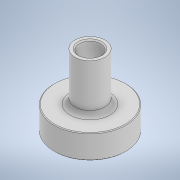
# Autodesk Inventor part: bague_portediodesimple
Saved by Autodesk Inventor 2021.5 (Build 255421000, 421)
## iProperties
Created: 2026-10-01
Part Number: bague_portediodesimple
Material: Générique
Document SubType Name: Modeling
Designer: Christophe
Density: 1 g/cm^3
Appearance: Par défaut
Author: Christophe
Autodesk Inventor part; units mm, degrees
ref_plane "YZ Plane" through (0, 0, 0) normal (1, 0, 0) x (0, 1, 0)
ref_plane "XZ Plane" through (0, 0, 0) normal (0, 1, 0) x (-1, 0, 0)
ref_plane "XY Plane" through (0, 0, 0) normal (0, 0, 1) x (1, 0, 0)
sketch "Esquisse1" plane through (0, 0, 0) normal (0, 1, 0) x (-1, 0, 0)
  circle A0 centre (0, 0) radius 15
  dimension "d0" = 30
  constraints: 1 centre point, 1 coincident
  measures "d0" diameter of A0
extrude "Extrusion1" add sketch "Esquisse1" along normal blind 10
chamfer "Chanfrein3" distance 0.3 angle 45 2 edges at (15, 10, 0) (15, 0, 0)
sketch "Esquisse3" plane through (0, 10, 0) normal (0, 1, 0) x (1, 0, 0)
  circle A0 centre (0, 0) radius 6.25
  dimension "d26" = 12.5
  constraints: 1 centre point, 1 coincident
  measures "d26" diameter of A0
extrude "Extrusion2" add sketch "Esquisse3" along normal blind 20
sketch "Esquisse4" plane through (0, 30, 0) normal (0, 1, 0) x (1, 0, 0)
  point P0 (0, 0)
hole "Perçage2" at (0, 30, 0) direction (0, -1, 0) diameter 5.1 end through all counterbore diameter 9 counterbore depth 27
chamfer "Chanfrein6" distance 0.5 angle 45 1 edges at (0, 0, -2.55)
chamfer "Chanfrein7" distance 0.2 angle 45 1 edges at (0, 3, -2.55)
chamfer "Chanfrein8" distance 0.5 angle 45 1 edges at (0, 30, -4.5)
fillet "Congé1" radius 2 1 edges at (-6.25, 10, 0)
